Autodesk Fusion 360 part; units mm, degrees
(part 2 of 2)
sketch "Esquisse5" plane through (0, 137.8397, 87.4866) normal (0, -0.844298, -0.535874) x (1, 0, 0)
  line L0 (9, -192.5257) -> (9, -162.5257)
  line L1 (9, -162.5257) -> (-9, -162.5257)
  line L2 (-9, -162.5257) -> (-9, -192.5257)
  line L3 (-9, -192.5257) -> (9, -192.5257)
  line L4 (-6, -169.9667) -> (6, -169.9667)
  line L5 (0, -187.5257) -> (4, -187.5257)
  line L6 (0, -187.5257) -> (-4, -187.5257)
  line L7 (-6, -169.9667) -> (-4, -187.5257)
  line L8 (6, -169.9667) -> (4, -187.5257)
  dimension "d40" = 3
  dimension "d41" = 3
  dimension "d42" = 7.441
  dimension "d58" = 4
  dimension "d59" = 4
  constraint perpendicular L2 L4
  constraint perpendicular L2 L5
  constraint parallel L5 L6
  measures "d40" distance of L0 L4.end
  measures "d41" distance of L2 L4.start
  measures "d42" distance of L1 L4
  measures "d58" distance of L5.start L5.end
  measures "d59" distance of L5.start L6.end
extrude "Extrusion5" cut sketch "Esquisse5" against normal blind 9 contours L4 L5 L6 L7 L8
sketch "Esquisse6" plane through (9, 0, 0) normal (1, 0, 0) x (0, 1, 0)
  circle A0 centre (195, 37) radius 1.5
  arc A1 (214.8949, -37.9318) -> (217.6293, -43.723) centre (222.3949, -37.9318) ccw
  line L0 (217.6293, -43.723) -> (224.9331, -49.7335)
  line L1 (224.9331, -49.7335) -> (241.0093, -75.0624)
  arc A2 (241.0093, -75.0624) -> (252.0093, -82.0624) centre (253.7621, -67.1652) ccw
  line L2 (252.0093, -82.0624) -> (252.0093, -77.0624)
  line L3 (252.0093, -77.0624) -> (256.0093, -75.0624)
  line L4 (256.0093, -75.0624) -> (252.0093, -73.0624)
  line L5 (252.0093, -73.0624) -> (252.0093, -70.3124)
  line L6 (252.0093, -70.3124) -> (256.0093, -68.3124)
  line L7 (256.0093, -68.3124) -> (252.0093, -66.3124)
  line L8 (252.0093, -66.3124) -> (252.0093, -63.5624)
  line L9 (252.0093, -63.5624) -> (256.0093, -61.5624)
  line L10 (256.0093, -61.5624) -> (252.0093, -59.5624)
  line L11 (252.0093, -59.5624) -> (252.0093, -56.8124)
  line L12 (252.0093, -56.8124) -> (256.0093, -54.8124)
  line L13 (256.0093, -54.8124) -> (252.0093, -52.8124)
  line L14 (252.0093, -52.8124) -> (252.0093, -50.0624)
  line L15 (252.0093, -50.0624) -> (256.0093, -48.0624)
  line L16 (256.0093, -48.0624) -> (252.0093, -46.0624)
  line L17 (252.0093, -46.0624) -> (252.0093, -32.0624)
  line L18 (252.0093, -32.0624) -> (260.5495, -26.8601)
  arc A3 (260.5495, -26.8601) -> (254.6108, -16.4326) centre (257.5802, -21.6463) ccw
  line L19 (254.6108, -16.4326) -> (245.9143, -21.3694)
  line L20 (245.9143, -21.3694) -> (226.596, -22.0875)
  line L21 (226.596, -22.0875) -> (212.245, 40.9935)
  arc A4 (212.245, 40.9935) -> (204.7733, 45.4393) centre (206.3945, 39.6625) ccw
  line L22 (204.7733, 45.4393) -> (194.4698, 42.5477)
  arc A5 (194.4698, 42.5477) -> (190.6271, 34.2919) centre (196.0911, 36.7709) ccw
  line L23 (190.6271, 34.2919) -> (216.6597, -23.0876)
  line L24 (216.6597, -23.0876) -> (218.7953, -28.3445)
  line L25 (218.7953, -28.3445) -> (217.7022, -29.2212)
  arc A6 (217.7022, -29.2212) -> (214.8949, -35.0717) centre (222.3949, -35.0717) ccw
  line L26 (214.8949, -35.0717) -> (214.8949, -37.9318)
  line L27 (249.3093, -75.0624) -> (234.3093, -50.0624)
  line L28 (234.3093, -50.0624) -> (249.3093, -50.0624)
  line L29 (249.3093, -50.0624) -> (249.3093, -75.0624)
  circle A7 centre (257.5802, -21.6463) radius 1.75
  circle A8 centre (219.0157, -36.5018) radius 1.75
  dimension "d50" = 3.5
  dimension "d51" = 3.5
  constraint concentric A3 A7
  measures "d50" diameter of A7
  measures "d51" diameter of A8
extrude "Extrusion6" add sketch "Esquisse6" along normal blind 1.5 contours A7 | A8
sketch "Esquisse7" plane through (9, 0, 0) normal (1, 0, 0) x (0, 1, 0)
  circle A0 centre (257.5802, -21.6463) radius 1.75
  circle A1 centre (219.0157, -36.5018) radius 1.75
  circle A2 centre (195, 37) radius 1.5
  arc A3 (214.8949, -37.9318) -> (217.6293, -43.723) centre (222.3949, -37.9318) ccw
  line L0 (217.6293, -43.723) -> (224.9331, -49.7335)
  line L1 (224.9331, -49.7335) -> (241.0093, -75.0624)
  arc A4 (241.0093, -75.0624) -> (252.0093, -82.0624) centre (253.7621, -67.1652) ccw
  line L2 (252.0093, -82.0624) -> (252.0093, -77.0624)
  line L3 (252.0093, -77.0624) -> (256.0093, -75.0624)
  line L4 (256.0093, -75.0624) -> (252.0093, -73.0624)
  line L5 (252.0093, -73.0624) -> (252.0093, -70.3124)
  line L6 (252.0093, -70.3124) -> (256.0093, -68.3124)
  line L7 (256.0093, -68.3124) -> (252.0093, -66.3124)
  line L8 (252.0093, -66.3124) -> (252.0093, -63.5624)
  line L9 (252.0093, -63.5624) -> (256.0093, -61.5624)
  line L10 (256.0093, -61.5624) -> (252.0093, -59.5624)
  line L11 (252.0093, -59.5624) -> (252.0093, -56.8124)
  line L12 (252.0093, -56.8124) -> (256.0093, -54.8124)
  line L13 (256.0093, -54.8124) -> (252.0093, -52.8124)
  line L14 (252.0093, -52.8124) -> (252.0093, -50.0624)
  line L15 (252.0093, -50.0624) -> (256.0093, -48.0624)
  line L16 (256.0093, -48.0624) -> (252.0093, -46.0624)
  line L17 (252.0093, -46.0624) -> (252.0093, -32.0624)
  line L18 (252.0093, -32.0624) -> (260.5495, -26.8601)
  arc A5 (260.5495, -26.8601) -> (254.6108, -16.4326) centre (257.5802, -21.6463) ccw
  line L19 (254.6108, -16.4326) -> (245.9143, -21.3694)
  line L20 (245.9143, -21.3694) -> (226.596, -22.0875)
  line L21 (226.596, -22.0875) -> (212.245, 40.9935)
  arc A6 (212.245, 40.9935) -> (204.7733, 45.4393) centre (206.3945, 39.6625) ccw
  line L22 (204.7733, 45.4393) -> (194.4698, 42.5477)
  arc A7 (194.4698, 42.5477) -> (190.6271, 34.2919) centre (196.0911, 36.7709) ccw
  line L23 (190.6271, 34.2919) -> (216.6597, -23.0876)
  line L24 (216.6597, -23.0876) -> (218.7953, -28.3445)
  line L25 (218.7953, -28.3445) -> (217.7022, -29.2212)
  arc A8 (217.7022, -29.2212) -> (214.8949, -35.0717) centre (222.3949, -35.0717) ccw
  line L26 (214.8949, -35.0717) -> (214.8949, -37.9318)
  line L27 (249.3093, -75.0624) -> (234.3093, -50.0624)
  line L28 (234.3093, -50.0624) -> (249.3093, -50.0624)
  line L29 (249.3093, -50.0624) -> (249.3093, -75.0624)
  line L30 (200.5702, 30.4647) -> (214.5883, -10.4529)
  arc A9 (214.5883, -10.4529) -> (221.1231, -8.2142) centre (217.8557, -9.3336) ccw
  line L31 (221.1231, -8.2142) -> (207.105, 32.7035)
  arc A10 (207.105, 32.7035) -> (200.5702, 30.4647) centre (203.8376, 31.5841) ccw
  line L32 (203.8376, 31.5841) -> (217.8557, -9.3336) construction
  constraint tangent L30 A9
  constraint tangent A9 L31
  constraint parallel L30 L31
  constraint tangent L31 A10
  constraint tangent L30 A10
extrude "Extrusion7" cut sketch "Esquisse7" against normal blind 1 contours L30 A9 L31 A10
ref_plane "Plan de construction1" through (0, 226.7509, -17.4594) normal (1, 0, 0) x (0, 1, 0)
mirror "Symétrie miroir1" about plane through (0, 226.7509, -17.4594) normal (1, 0, 0) of "Extrusion6", "Extrusion7"
